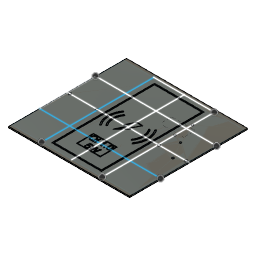
Top panel (Autodesk Fusion 360 design; units mm, degrees)
Autodesk Fusion 360 part; units mm, degrees
sketch "Sketch1" plane through (0, 0, 0) normal (0, 0, 1) x (1, 0, 0)
  line L0 (0, 0) -> (205, 0)
  line L1 (205, 0) -> (205, 190)
  line L2 (205, 190) -> (0, 190)
  line L3 (0, 190) -> (0, 0)
  dimension "d1" = 205
  dimension "d2" = 190
  constraint horizontal L0
  constraint vertical L1
  constraint horizontal L2
  constraint vertical L3
  constraint coincident L0.start L3.end
  measures "d1" distance of L0.start L0.end
  measures "d2" distance of L0.start L2.end
extrude "Extrude1" add sketch "Sketch1" along normal blind 2
extrude "Extrude2" add 1 faces at (68.3333, 126.6667, 2) along direction (0, 0, 1) blind 1
sketch "Sketch2" plane through (0, 0, 3) normal (0, 0, 1) x (-1, 0, 0)
  line L0 (0, -190) -> (0, 0)
  line L1 (0, 0) -> (-205, 0)
  line L2 (-205, 0) -> (-205, -190)
  line L3 (-205, -190) -> (0, -190)
  line L4 (-102.5, -190) -> (-102.5, 0)
  line L5 (0, -95) -> (-205, -95)
  line L6 (-102.5, -190) -> (-153.75, -190)
  line L7 (-153.75, -190) -> (-153.75, 0)
  line L8 (-102.5, -190) -> (-51.25, -190)
  line L9 (-51.25, -190) -> (-51.25, 0)
  line L10 (0, -95) -> (0, -142.5)
  line L11 (0, -95) -> (0, -47.5)
  line L12 (0, -142.5) -> (-205, -142.5)
  line L13 (0, -47.5) -> (-205, -47.5)
  dimension "d7" = 51.25
  dimension "d8" = 90
  dimension "d9" = 47.5
  constraint midpoint L3 L4.start
  constraint midpoint L1 L4.end
  constraint midpoint L0 L5.start
  constraint midpoint L2 L5.end
  constraint coincident L3 L6.end
  constraint coincident L1 L7.end
  constraint perpendicular L1 L7
  constraint coincident L1 L9.end
  constraint perpendicular L1 L9
  constraint coincident L0 L10.end
  constraint perpendicular L5 L11
  constraint coincident L2 L12.end
  constraint perpendicular L2 L12
  constraint coincident L2 L13.end
  constraint perpendicular L2 L13
  measures "d7" distance of L4.start L6.end
  measures "d8" angle of L7 L8
  measures "d9" distance of L5.start L10.end
sketch "Sketch3" plane through (0, 0, 3) normal (0, 0, 1) x (-1, 0, 0)
  line L0 (-62.5, -10) -> (-142.5, -10)
  line L1 (-142.5, -10) -> (-142.5, -180)
  line L2 (-142.5, -180) -> (-62.5, -180)
  line L3 (-62.5, -180) -> (-62.5, -10)
  line L4 (-62.5, -10) -> (-142.5, -180) construction
  line L5 (-142.5, -10) -> (-62.5, -180) construction
  line L6 (-144.5, -8) -> (-60.5, -8)
  line L7 (-60.5, -8) -> (-60.5, -182)
  line L8 (-60.5, -182) -> (-144.5, -182)
  line L9 (-144.5, -182) -> (-144.5, -8)
  line L10 (-144.5, -8) -> (-60.5, -182) construction
  line L11 (-60.5, -8) -> (-144.5, -182) construction
  point P0 (-102.5, -95)
  point P1 (-102.5, -95)
  dimension "d10" = 80
  dimension "d11" = 170
  dimension "d12" = 84
  dimension "d13" = 174
  constraint horizontal L0
  constraint perpendicular L0 L1
  constraint parallel L0 L2
  constraint parallel L1 L3
  constraint coincident L4 P1
  constraint coincident L5 P1
  constraint horizontal L6
  constraint perpendicular L6 L7
  constraint parallel L6 L8
  constraint parallel L7 L9
  constraint coincident L10 P1
  constraint coincident L11 P1
  constraint coincident P1 P0
  measures "d10" distance of L1.end L2.end
  measures "d11" distance of L0.end L1.end
  measures "d12" distance of L7.end L8.end
  measures "d13" distance of L6.end L7.end
extrude "Extrude3" cut sketch "Sketch3" against normal blind 1
sketch "Sketch4" plane through (0, 0, 3) normal (0, 0, 1) x (-1, 0, 0)
  circle A0 centre (-102.5, -95) radius 25
  circle A1 centre (-102.5, -95) radius 27
  circle A2 centre (-102.5, -95) radius 32.5
  circle A3 centre (-102.5, -95) radius 34.5
  line L0 (-74.5889, -74.7214) -> (-130.4111, -115.2786)
  line L1 (-102.5, -95) -> (-68, -95) construction
  line L2 (-74.5889, -115.2786) -> (-130.4111, -74.7214)
  line L3 (-102.5, -95) -> (-68, -95) construction
  dimension "d16" = 50
  dimension "d17" = 54
  dimension "d18" = 65
  dimension "d19" = 69
  dimension "d20" = 144
  dimension "d21" = 69
  dimension "d22" = 144
  constraint concentric A0 A1
  constraint concentric A1 A2
  constraint concentric A2 A3
  constraint midpoint L0 A0.centre
  constraint horizontal L1
  constraint coincident A0.centre A1.centre
  constraint midpoint L2 A0.centre
  constraint horizontal L3
  measures "d16" diameter of A0
  measures "d17" diameter of A1
  measures "d18" diameter of A2
  measures "d19" diameter of A3
  measures "d20" angle of L0 L1
  measures "d21" distance of L0.start L0.end
  measures "d22" angle of L2 L3
extrude "Extrude4" cut sketch "Sketch4" against normal blind 0.8 contours A0 A1 L0 L2 | A0 A1 L0 L2 | A2 A3 L0 L2 | A2 A3 L0 L2 picked at (-80.5903, -80.4759) picked at (-124.4695, -109.4135) picked at (-71.6575, -108.7616) picked at (-131.5229, -112.2444)
sketch "Sketch5" plane through (0, 0, 3) normal (0, 0, 1) x (-1, 0, 0)
  line L0 (-112.5, -110) -> (-102.5, -110)
  line L1 (-102.5, -110) -> (-95, -95)
  line L2 (-95, -95) -> (-100, -95)
  line L3 (-100, -95) -> (-92.5, -80)
  line L4 (-92.5, -80) -> (-107.5, -95)
  line L5 (-107.5, -95) -> (-104.5, -95)
  line L6 (-104.5, -95) -> (-112.5, -110)
  dimension "d25" = 5
  constraint horizontal L0
  constraint parallel L0 L2
  constraint parallel L1 L3
  constraint parallel L2 L5
  measures "d25" distance of L1.end L2.end
extrude "Extrude5" cut sketch "Sketch5" against normal blind 0.8
sketch "Sketch6" plane through (0, 0, 0) normal (0, 0, -1) x (1, 0, 0)
  line L0 (0, 0) -> (0, -190)
  line L1 (0, -190) -> (205, -190)
  line L2 (205, -190) -> (205, 0)
  line L3 (205, 0) -> (0, 0)
  circle A0 centre (102.5, -95) radius 25.5
  line L4 (131.75, -89) -> (127.25, -89)
  line L5 (127.25, -89) -> (127.25, -101)
  line L6 (127.25, -101) -> (131.75, -101)
  line L7 (131.75, -101) -> (131.75, -89)
  line L8 (131.75, -89) -> (127.25, -101) construction
  line L9 (127.25, -89) -> (131.75, -101) construction
  point P0 (129.5, -95)
  dimension "d28" = 51
  dimension "d29" = 4.5
  dimension "d30" = 12
  constraint horizontal L4
  constraint perpendicular L4 L5
  constraint parallel L4 L6
  constraint parallel L5 L7
  constraint coincident L8 P0
  constraint coincident L9 P0
  measures "d28" diameter of A0
  measures "d29" distance of L5.end L6.end
  measures "d30" distance of L4.end L5.end
extrude "Extrude6" cut sketch "Sketch6" against normal blind 1.5 contours A0 L4 L5 L6 | A0 L4 L6 L7 | A0 L4 L5 L6
sketch "Sketch7" plane through (0, 0, 0) normal (0, 0, -1) x (1, 0, 0)
  line L0 (127.2841, -89) -> (131.75, -89)
  line L1 (131.75, -89) -> (131.75, -101)
  line L2 (131.75, -101) -> (127.2841, -101)
  arc A0 (127.2841, -89) -> (127.2841, -101) centre (102.5, -95) ccw
  line L3 (0, 0) -> (0, -190)
  line L4 (0, -190) -> (205, -190)
  line L5 (205, -190) -> (205, 0)
  line L6 (205, 0) -> (0, 0)
  line L7 (151.75, -120.25) -> (168.25, -120.25)
  line L8 (168.25, -120.25) -> (168.25, -149.75)
  line L9 (168.25, -149.75) -> (151.75, -149.75)
  line L10 (151.75, -149.75) -> (151.75, -120.25)
  line L11 (151.75, -120.25) -> (168.25, -149.75) construction
  line L12 (168.25, -120.25) -> (151.75, -149.75) construction
  circle A1 centre (151.75, -149.75) radius 1.7
  circle A2 centre (168.25, -120.25) radius 1.7
  point P0 (160, -135)
  dimension "d33" = 16.5
  dimension "d34" = 29.5
  dimension "d35" = 3.4
  dimension "d36" = 3.4
  constraint horizontal L7
  constraint perpendicular L7 L8
  constraint parallel L7 L9
  constraint parallel L8 L10
  constraint coincident L11 P0
  constraint coincident L12 P0
  constraint coincident L9.end L10.start
  constraint coincident L7.end L8.start
  measures "d33" distance of L8.end L9.end
  measures "d34" distance of L7.end L8.end
  measures "d35" diameter of A1
  measures "d36" diameter of A2
extrude "Extrude7" cut sketch "Sketch7" against normal blind 3 contours L7 L8 A2 | L7 L8 A2 | L9 L10 A1 | L9 L10 A1
sketch "Sketch8" plane through (0, 0, 0) normal (0, 0, -1) x (1, 0, 0)
  circle A0 centre (151.75, -149.75) radius 1.7
  circle A1 centre (168.25, -120.25) radius 1.7
  line L0 (127.2841, -89) -> (131.75, -89)
  line L1 (131.75, -89) -> (131.75, -101)
  line L2 (131.75, -101) -> (127.2841, -101)
  arc A2 (127.2841, -89) -> (127.2841, -101) centre (102.5, -95) ccw
  line L3 (0, 0) -> (0, -190)
  line L4 (0, -190) -> (205, -190)
  line L5 (205, -190) -> (205, 0)
  line L6 (205, 0) -> (0, 0)
  circle A3 centre (151.75, -149.75) radius 2.5
  circle A4 centre (168.25, -120.25) radius 2.5
  dimension "d39" = 5
  dimension "d40" = 5
  constraint concentric A0 A3
  constraint concentric A1 A4
  measures "d39" diameter of A3
  measures "d40" diameter of A4
extrude "Extrude8" add sketch "Sketch8" along normal blind 2 contours A3 | A4
sketch "Sketch9" plane through (0, 0, 3) normal (0, 0, 1) x (-1, 0, 0)
  line L0 (-70, -35) -> (-134.9905, -35.7868) construction
  line L1 (-134.9905, -35.7868) -> (-134.7506, -55.6023) construction
  line L2 (-134.7506, -55.6023) -> (-69.7601, -54.8155) construction
  line L3 (-69.7601, -54.8155) -> (-70, -35) construction
  dimension "d43" = 10
  text T0 "Qi 1.0\n5W" font "Arial" height 10 align centre top in box 64.9952 x 19.8169 at (-70, -35) x (-0.999927, -0.012106) y (0.012106, -0.999927) spacing 1 kerned
extrude "Extrude9" cut sketch "Sketch9" against normal blind 0.8 text T0
sketch "Sketch10" plane through (0, 0, 3) normal (0, 0, 1) x (-1, 0, 0)
  line L0 (-83, -56) -> (-121.5, -56)
  line L1 (-121.5, -56) -> (-121.5, -29)
  line L2 (-121.5, -29) -> (-83, -29)
  line L3 (-83, -29) -> (-83, -56)
  line L4 (-122.25, -28.25) -> (-82.25, -28.25)
  line L5 (-82.25, -28.25) -> (-82.25, -56.75)
  line L6 (-82.25, -56.75) -> (-122.25, -56.75)
  line L7 (-122.25, -56.75) -> (-122.25, -28.25)
  line L8 (-122.25, -28.25) -> (-82.25, -56.75) construction
  line L9 (-82.25, -28.25) -> (-122.25, -56.75) construction
  point P0 (-102.25, -42.5)
  dimension "d47" = 40
  dimension "d48" = 28.5
  constraint horizontal L0
  constraint vertical L1
  constraint horizontal L2
  constraint vertical L3
  constraint horizontal L4
  constraint perpendicular L4 L5
  constraint parallel L4 L6
  constraint parallel L5 L7
  constraint coincident L8 P0
  constraint coincident L9 P0
  measures "d47" distance of L5.end L6.end
  measures "d48" distance of L4.end L5.end
extrude "Extrude10" cut sketch "Sketch10" against normal blind 1
sketch "Sketch11" plane through (0, 0, 3) normal (0, 0, 1) x (1, 0, 0)
  line L0 (0, 95) -> (4, 95)
  line L1 (205, 95) -> (201, 95)
  circle A0 centre (201, 95) radius 2.1
  circle A1 centre (4, 95) radius 2.1
  dimension "d51" = 4
  dimension "d52" = 4
  dimension "d53" = 4.2
  dimension "d54" = 4.2
  constraint horizontal L0
  constraint horizontal L1
  constraint coincident L1.end A0.centre
  constraint coincident L0.end A1.centre
  measures "d51" distance of L0.start L0.end
  measures "d52" distance of L1.start L1.end
  measures "d53" diameter of A0
  measures "d54" diameter of A1
extrude "Extrude11" cut sketch "Sketch11" against normal blind 3
extrude "Extrude12" add 1 faces at (136.6667, 190, 1) along direction (0, 1, 0) blind 5
extrude "Extrude13" add 1 faces at (68.3333, 0, 1) along direction (0, -1, 0) blind 5
sketch "Sketch12" plane through (0, 0, 3) normal (0, 0, 1) x (-1, 0, 0)
  line L0 (-50, -90) -> (-155, -90)
  line L1 (-155, -90) -> (-155, -100)
  line L2 (-155, -100) -> (-50, -100)
  line L3 (-50, -100) -> (-50, -90)
  line L4 (-50, -90) -> (-155, -100) construction
  line L5 (-155, -90) -> (-50, -100) construction
  circle A0 centre (-155, -95) radius 2.1
  circle A1 centre (-50, -95) radius 2.1
  point P0 (-102.5, -95)
  dimension "d61" = 105
  dimension "d62" = 10
  dimension "d63" = 4.2
  dimension "d64" = 4.2
  constraint horizontal L0
  constraint perpendicular L0 L1
  constraint parallel L0 L2
  constraint parallel L1 L3
  constraint coincident L4 P0
  constraint coincident L5 P0
  constraint midpoint L1 A0.centre
  constraint midpoint L3 A1.centre
  measures "d61" distance of L1.end L2.end
  measures "d62" distance of L0.end L1.end
  measures "d63" diameter of A0
  measures "d64" diameter of A1
extrude "Extrude14" cut sketch "Sketch12" against normal blind 3 contours L3 A1 | L3 A1 | L1 A0 | L1 A0
sketch "Sketch13" plane through (0, 0, 1.5) normal (0, 0, -1) x (1, 0, 0)
  line L0 (131.75, -101) -> (131.75, -89)
  line L1 (131.75, -89) -> (127.2841, -89)
  arc A0 (127.2841, -89) -> (127.2841, -101) centre (102.5, -95) ccw
  line L2 (127.2841, -101) -> (131.75, -101)
  circle A1 centre (102.5, -95) radius 25.5
  line L3 (131.75, -89) -> (127.2841, -89)
  line L4 (127.2841, -89) -> (127.2841, -101)
  line L5 (127.2841, -101) -> (131.75, -101)
  line L6 (131.75, -101) -> (131.75, -89)
  constraint concentric A0 A1
  constraint horizontal L3
  constraint vertical L4
  constraint horizontal L5
  constraint vertical L6
  constraint coincident A0.end L2.start
  constraint coincident L0.end L1.start
extrude "Extrude15" add sketch "Sketch13" along normal blind 1.5 contours L0 L1 L2 A1 L3 L5 L6
sketch "Sketch14" plane through (0, 0, 0) normal (0, 0, -1) x (1, 0, 0)
  line L0 (0, 5) -> (0, -195)
  line L1 (0, -195) -> (205, -195)
  line L2 (205, -195) -> (205, 5)
  line L3 (205, 5) -> (0, 5)
  circle A0 centre (102.5, -95) radius 25.5
  circle A1 centre (151.75, -149.75) radius 2.5
  circle A2 centre (168.25, -120.25) radius 2.5
  circle A3 centre (201, -95) radius 2.1
  circle A4 centre (4, -95) radius 2.1
  circle A5 centre (155, -95) radius 2.1
  circle A6 centre (50, -95) radius 2.1
  line L4 (107.5, -120) -> (97.5, -120)
  line L5 (97.5, -120) -> (97.5, -123)
  line L6 (97.5, -123) -> (107.5, -123)
  line L7 (107.5, -123) -> (107.5, -120)
  line L8 (107.5, -120) -> (97.5, -123) construction
  line L9 (97.5, -120) -> (107.5, -123) construction
  point P0 (102.5, -121.5)
  dimension "d69" = 10
  dimension "d70" = 3
  constraint horizontal L4
  constraint perpendicular L4 L5
  constraint parallel L4 L6
  constraint parallel L5 L7
  constraint coincident L8 P0
  constraint coincident L9 P0
  measures "d69" distance of L5.end L6.end
  measures "d70" distance of L4.end L5.end
extrude "Extrude16" cut sketch "Sketch14" against normal blind 1.5 contours A0 L5 L6 L7
sketch "Sketch15" plane through (0, 0, 0) normal (0, 0, -1) x (1, 0, 0)
  line L0 (97.5, -123) -> (97.5, -120.005)
  arc A0 (107.5, -120.005) -> (97.5, -120.005) centre (102.5, -95) ccw
  line L1 (107.5, -120.005) -> (107.5, -123)
  line L2 (107.5, -123) -> (97.5, -123)
  line L3 (0, 5) -> (0, -195)
  line L4 (0, -195) -> (205, -195)
  line L5 (205, -195) -> (205, 5)
  line L6 (205, 5) -> (0, 5)
  circle A1 centre (151.75, -149.75) radius 2.5
  circle A2 centre (168.25, -120.25) radius 2.5
  circle A3 centre (201, -95) radius 2.1
  circle A4 centre (4, -95) radius 2.1
  circle A5 centre (155, -95) radius 2.1
  circle A6 centre (50, -95) radius 2.1
  circle A7 centre (168.25, -120.25) radius 1.7
  circle A8 centre (151.75, -149.75) radius 1.7
  dimension "d73" = 3.4
  dimension "d74" = 3.4
  constraint concentric A2 A7
  constraint concentric A1 A8
  measures "d73" diameter of A7
  measures "d74" diameter of A8
extrude "Extrude17" cut 2 faces at (167.5531, 122.3657, -2) (151.134, 151.8906, -2) along direction (0, 0, 1) blind 2
extrude "Extrude18" add sketch "Sketch15" against normal blind 3 contours A7 | A8
sketch "Sketch16" plane through (0, 0, 0) normal (0, 0, -1) x (1, 0, 0)
  line L0 (97.5, -123) -> (97.5, -120.005)
  arc A0 (107.5, -120.005) -> (97.5, -120.005) centre (102.5, -95) ccw
  line L1 (107.5, -120.005) -> (107.5, -123)
  line L2 (107.5, -123) -> (97.5, -123)
  line L3 (0, 5) -> (0, -195)
  line L4 (0, -195) -> (205, -195)
  line L5 (205, -195) -> (205, 5)
  line L6 (205, 5) -> (0, 5)
  circle A1 centre (201, -95) radius 2.1
  circle A2 centre (4, -95) radius 2.1
  circle A3 centre (155, -95) radius 2.1
  circle A4 centre (50, -95) radius 2.1
  circle A5 centre (153.75, -123) radius 1.7
  line L7 (153.75, -123) -> (153.75, -153)
  circle A6 centre (153.75, -153) radius 1.7
  dimension "d79" = 3.4
  dimension "d80" = 30
  dimension "d81" = 3.4
  constraint coincident A5.centre L7.start
  constraint vertical L7
  constraint coincident L7.end A6.centre
  measures "d79" diameter of A5
  measures "d80" distance of A5.centre L7.end
  measures "d81" diameter of A6
sketch "Sketch17" plane through (0, 0, 0) normal (0, 0, -1) x (1, 0, 0)
  line L0 (143.75, -153) -> (143.75, -138)
  line L1 (163.75, -148) -> (123.75, -148)
  line L2 (123.75, -148) -> (123.75, -128)
  line L3 (123.75, -128) -> (163.75, -128)
  line L4 (163.75, -128) -> (163.75, -148)
  line L5 (163.75, -148) -> (123.75, -128) construction
  line L6 (123.75, -148) -> (163.75, -128) construction
  point P0 (143.75, -138)
  dimension "d82" = 15
  dimension "d83" = 40
  dimension "d84" = 20
  constraint vertical L0
  constraint horizontal L1
  constraint perpendicular L1 L2
  constraint parallel L1 L3
  constraint parallel L2 L4
  constraint coincident L5 P0
  constraint coincident L6 P0
  constraint coincident P0 L0.end
  measures "d82" distance of L0.start P0
  measures "d83" distance of L2.end L3.end
  measures "d84" distance of L1.end L2.end
extrude "Extrude19" cut sketch "Sketch17" against normal blind 1.2
extrude "Extrude20" cut sketch "Sketch16" against normal blind 754654 contours A5 | A6
sketch "Sketch18" plane through (0, 0, 0) normal (0, 0, -1) x (1, 0, 0)
  circle A0 centre (50, -95) radius 2.1
  circle A1 centre (155, -95) radius 2.1
  circle A2 centre (4, -95) radius 2.1
  circle A3 centre (201, -95) radius 2.1
  line L0 (0, 5) -> (0, -195)
  line L1 (0, -195) -> (205, -195)
  line L2 (205, -195) -> (205, 5)
  line L3 (205, 5) -> (0, 5)
  line L4 (97.5, -123) -> (97.5, -120.005)
  arc A4 (107.5, -120.005) -> (97.5, -120.005) centre (102.5, -95) ccw
  line L5 (107.5, -120.005) -> (107.5, -123)
  line L6 (107.5, -123) -> (97.5, -123)
  line L7 (123.75, -148) -> (123.75, -128)
  line L8 (123.75, -128) -> (163.75, -128)
  line L9 (163.75, -128) -> (163.75, -148)
  line L10 (163.75, -148) -> (123.75, -148)
  circle A5 centre (153.75, -153) radius 1.7
  circle A6 centre (153.75, -123) radius 1.7
  line L11 (165, -125) -> (190, -125)
  line L12 (190, -125) -> (190, -80)
  line L13 (190, -80) -> (165, -80)
  line L14 (165, -80) -> (165, -125)
  line L15 (177.5, -80) -> (177.5, -125)
  line L16 (165, -102.5) -> (190, -102.5)
  line L17 (185.6, -117) -> (169.4, -117)
  line L18 (169.4, -117) -> (169.4, -88)
  line L19 (169.4, -88) -> (185.6, -88)
  line L20 (185.6, -88) -> (185.6, -117)
  line L21 (185.6, -117) -> (169.4, -88) construction
  line L22 (169.4, -117) -> (185.6, -88) construction
  circle A7 centre (185.6, -88) radius 1.7
  circle A8 centre (169.4, -117) radius 1.7
  point P0 (177.5, -102.5)
  dimension "d89" = 25
  dimension "d90" = 45
  dimension "d91" = 16.2
  dimension "d92" = 29
  dimension "d93" = 3.4
  dimension "d94" = 3.4
  constraint horizontal L11
  constraint vertical L12
  constraint horizontal L13
  constraint vertical L14
  constraint midpoint L13 L15.start
  constraint midpoint L11 L15.end
  constraint midpoint L14 L16.start
  constraint midpoint L12 L16.end
  constraint horizontal L17
  constraint perpendicular L17 L18
  constraint parallel L17 L19
  constraint parallel L18 L20
  constraint coincident L21 P0
  constraint coincident L22 P0
  constraint midpoint L15 P0
  constraint coincident L19.end L20.start
  constraint coincident L17.end L18.start
  measures "d89" distance of L11.start L11.end
  measures "d90" distance of L11.start L13.end
  measures "d91" distance of L18.end L19.end
  measures "d92" distance of L17.end L18.end
  measures "d93" diameter of A7
  measures "d94" diameter of A8
extrude "Extrude21" cut sketch "Sketch18" against normal blind 3 contours L17 L18 A8 | L17 L18 A8 | L19 L20 A7 | L19 L20 A7
sketch "Sketch19" plane through (0, 0, 0) normal (0, 0, -1) x (1, 0, 0)
  circle A0 centre (153.75, -123) radius 1.7
  circle A1 centre (153.75, -153) radius 1.7
  line L0 (123.75, -148) -> (123.75, -128)
  line L1 (123.75, -128) -> (163.75, -128)
  line L2 (163.75, -128) -> (163.75, -148)
  line L3 (163.75, -148) -> (123.75, -148)
  line L4 (97.5, -123) -> (97.5, -120.005)
  arc A2 (107.5, -120.005) -> (97.5, -120.005) centre (102.5, -95) ccw
  line L5 (107.5, -120.005) -> (107.5, -123)
  line L6 (107.5, -123) -> (97.5, -123)
  line L7 (0, 5) -> (0, -195)
  line L8 (0, -195) -> (205, -195)
  line L9 (205, -195) -> (205, 5)
  line L10 (205, 5) -> (0, 5)
  circle A3 centre (201, -95) radius 2.1
  circle A4 centre (4, -95) radius 2.1
  circle A5 centre (155, -95) radius 2.1
  circle A6 centre (50, -95) radius 2.1
  circle A7 centre (169.4, -117) radius 1.7
  circle A8 centre (185.6, -88) radius 1.7
  circle A9 centre (185.6, -88) radius 2.5
  circle A10 centre (169.4, -117) radius 2.5
  dimension "d97" = 5
  dimension "d98" = 5
  constraint concentric A8 A9
  constraint concentric A7 A10
  measures "d97" diameter of A9
  measures "d98" diameter of A10
extrude "Extrude22" add sketch "Sketch19" along normal blind 1 contours A9 | A10
extrude "Extrude23" cut 1 faces at (104.8389, 87.338, 1.5) along direction (0, 0, 1) blind 0.5
extrude "Extrude24" cut 1 faces at (137.0833, 134.6667, 1.2) along direction (0, 0, 1) blind 0.5
extrude "Extrude25" cut 1 faces at (102.5, 19.8333, 0) along direction (0, 0, 1) blind 1
extrude "Extrude26" cut 2 faces at (170.4045, 118.9882, -1) (184.9031, 90.1157, -1) along direction (0, 0, 1) blind 2
extrude "Extrude27" add 1 faces at (104.8389, 87.338, 2) along direction (0, 0, -1) blind 0.5
equation "d7 = ( 102.500 / 2 ) * 1 mm"
equation "d9 = ( 95.000 / 2 ) * 1 mm"
equation "d44 = 'Qi 1.0 5W'"
equation "d47 = 38.500 mm + ( ( 0.75 * 2 ) * 1 mm )"
equation "d48 = 27 mm + 0.75 * 2 mm"
equation "d51 = 1.9 mm + 2.1 mm"
equation "d52 = 1.9 mm + 2.1 mm"
